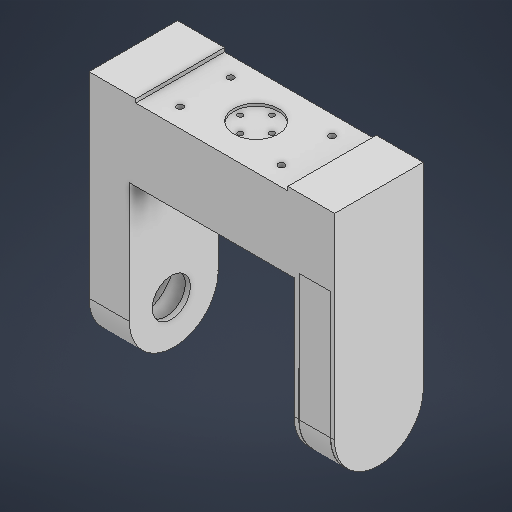
# Autodesk Inventor part: U_support
Saved by Autodesk Inventor 2026.1 (Build 301233020, 233B)
## iProperties
Created: 2026-11-17
Part Number: U_support
Material: Generic
Document SubType Name: Modeling
Designer: matar
Density: 1 g/cm^3
Appearance: Default
Author: matar
Autodesk Inventor part; units mm, degrees
ref_plane "YZ Plane" through (0, 0, 0) normal (1, 0, 0) x (0, 1, 0)
ref_plane "XZ Plane" through (0, 0, 0) normal (0, 1, 0) x (-1, 0, 0)
ref_plane "XY Plane" through (0, 0, 0) normal (0, 0, 1) x (1, 0, 0)
sketch "Sketch1" plane through (0, 0, 0) normal (0, 1, 0) x (-1, 0, 0)
  line L0 (0, 0) -> (130, 0)
  line L1 (130, 0) -> (130, -70)
  line L2 (130, -70) -> (0, -70)
  line L3 (0, -70) -> (0, 0)
  dimension "d0" = 130
  dimension "d1" = 70
  constraints: 8 end point, 2 parallel, 1 horizontal, 1 perpendicular
  measures "d0" distance of L1.end L2.end
  measures "d1" distance of L0.end L1.end
extrude "Extrusion1" add sketch "Sketch1" along normal blind 5
sketch "Sketch4" plane through (0, 0, 0) normal (1, 0, 0) x (0, 0, -1)
  line L0 (70, 5) -> (0, 5) projected
  line L1 (70, 5) -> (0, 5)
  line L2 (0, 5) -> (0, -95)
  line L3 (70, 5) -> (70, -95)
  arc A0 (0, -95) -> (70, -95) centre (35, -95) ccw
  point P0 (0, 0)
  dimension "d10" = 100
  constraints: 6 end point, 2 point on circle, 2 tangent, 1 centre point, 1 collinear, 1 perpendicular, 1 vertical
  measures "d10" distance of L0.start L3.end
sketch "Sketch5" plane through (-130, 0, -70) normal (-1, 0, 0) x (0, 0, 1)
  line L0 (0, 5) -> (70, 5) projected
  line L1 (70, -95) -> (70, 5)
  line L2 (70, 5) -> (0, 5)
  line L3 (0, 5) -> (0, -95)
  arc A0 (0, -95) -> (70, -95) centre (35, -95) ccw
  point P0 (70, 0)
  dimension "d8" = 100
  dimension "d9" = 35
  constraints: 6 end point, 2 perpendicular, 2 point on circle, 2 tangent, 1 centre point, 1 vertical
  measures "d8" distance of L1.start L0.end
  measures "d9" radius of A0
extrude "Extrusion2" add sketch "Sketch5" along normal blind 4
extrude "Extrusion3" add sketch "Sketch4" along normal blind 4
sketch "Sketch6" plane through (-134, 0, -70) normal (-1, 0, 0) x (0, 0, 1)
  line L0 (0, -95) -> (0, 5) projected
  line L1 (0, 5) -> (0, -95)
  line L2 (70, 5) -> (70, -95)
  arc A0 (0, -95) -> (70, -95) centre (35, -95) ccw projected
  arc A1 (0, -95) -> (70, -95) centre (35, -95) ccw
  arc A2 (5, -99.3497) -> (65, -99.3497) centre (35, -95) ccw
  line L3 (0, 5) -> (5, 5)
  line L4 (5, 5) -> (5, -99.3497)
  line L5 (0, 5) -> (5, 5)
  line L6 (70, 5) -> (65, 5)
  line L7 (65, 5) -> (65, -99.3497)
  line L8 (0, 5) -> (70, 5) projected
  dimension "d13" = 5
  dimension "d14" = 5
  constraints: 14 end point, 4 point on circle, 2 centre point, 2 concentric, 2 perpendicular, 1 collinear, 1 point on line
  measures "d13" distance of L0.end L3.end
  measures "d14" distance of L2.start L6.end
extrude "Extrusion4" add sketch "Sketch6" along normal blind 25 contours L0 L3 L4 A2 L7 L6 L2 A0
sketch "Sketch7" plane through (4, 0, 0) normal (1, 0, 0) x (0, 0, -1)
  line L0 (-0.1762, -95) -> (0, 5)
  line L1 (0, 5) -> (-0.1762, -95)
  line L2 (70, 5) -> (70, -98.5163)
  arc A0 (-0.1762, -95) -> (70, -98.5163) centre (35, -95) ccw
  arc A1 (-0.1762, -95) -> (70, -98.5163) centre (35, -95) ccw
  arc A2 (5, -99.3497) -> (65, -99.3497) centre (35, -95) ccw
  line L3 (0, 5) -> (5, 5)
  line L4 (5, 5) -> (5, -99.3497)
  line L5 (0, 5) -> (5, 5)
  line L6 (70, 5) -> (65, 5)
  line L7 (65, 5) -> (65, -99.3497)
  line L8 (0, 5) -> (70, 5)
  line L9 (70, -95) -> (70, 5) projected
  line L10 (70, 5) -> (0, 5) projected
  point P0 (0, 0)
  dimension "d15" = 5
  dimension "d16" = 5
  dimension "d17" = 0
  dimension "d18" = 0
  constraints: 18 end point, 6 point on circle, 3 centre point, 2 concentric, 2 perpendicular, 1 collinear, 1 point on line
  measures "d15" distance of L0.end L3.end
  measures "d16" distance of L2.start L6.end
  measures "d17" distance between parallel lines of L2 L9
  measures "d18" distance between parallel lines of L10 L8
extrude "Extrusion5" add sketch "Sketch7" along normal blind 25 contours L0 L3 L4 A2 L7 L6 L2 A0
sketch "Sketch8" plane through (-159, 0, -70) normal (-1, 0, 0) x (0, 0, 1)
  line L0 (0, 0) -> (0, -95) projected
  line L1 (0, -95) -> (0, 5)
  line L2 (70, -95) -> (70, 5) projected
  line L3 (0, 5) -> (70, 5)
  line L4 (70, 5) -> (70, -95)
  arc A0 (0, -95) -> (70, -95) centre (35, -95) ccw projected
  arc A1 (0, -95) -> (70, -95) centre (35, -95) ccw
  arc A2 (5, -99.3497) -> (65, -99.3497) centre (35, -95) ccw projected
  point P0 (70, 0)
  constraints: 6 end point, 3 point on circle, 1 centre point, 1 collinear, 1 concentric, 1 perpendicular, 1 point on line
extrude "Extrusion6" add sketch "Sketch8" along normal blind 3
sketch "Sketch9" plane through (29, 0, 0) normal (1, 0, 0) x (0, 0, -1)
  line L0 (0, -95) -> (0, 0) projected
  line L1 (0, 5) -> (70, 5) projected
  line L2 (0, -95) -> (0, 5)
  line L3 (0, 5) -> (70, 5)
  line L4 (70, 5) -> (70, -95)
  arc A0 (0, -95) -> (70, -95) centre (35, -95) ccw projected
  arc A1 (0, -95) -> (70, -95) centre (35, -95) ccw
  point P0 (0, 0)
  constraints: 6 end point, 3 point on circle, 1 centre point, 1 collinear, 1 concentric, 1 perpendicular, 1 vertical
extrude "Extrusion7" add sketch "Sketch9" along normal blind 3
sketch "Sketch10" plane through (-130, 0, -70) normal (1, 0, 0) x (0, 0, -1)
  circle A0 centre (-37, -95) radius 15
  arc A1 (-70, -95) -> (0, -95) centre (-35, -95) ccw projected
  point P0 (-70, 0)
  dimension "d25" = 30
  dimension "d26" = 0
  constraints: 1 centre point
  measures "d25" diameter of A0
  measures "d26" vertical distance of A1.centre A0.centre
extrude "Extrusion8" cut sketch "Sketch10" against normal blind 5
sketch "Sketch11" plane through (0, 0, 0) normal (-1, 0, 0) x (0, 0, 1)
  circle A0 centre (-35, -95) radius 15
  arc A1 (-70, -95) -> (0, -95) centre (-35, -95) ccw projected
  line L0 (0, 0) -> (0, -95) projected
  dimension "d29" = 30
  dimension "d30" = 0
  dimension "d31" = 35
  constraints: 1 centre point
  measures "d29" diameter of A0
  measures "d30" distance of A1.centre A0.centre
  measures "d31" distance from line of L0 A0.centre
extrude "Extrusion9" cut sketch "Sketch11" against normal blind 6
sketch "Sketch12" plane through (0, 5, 0) normal (0, 1, 0) x (1, 0, 0)
  line L0 (4, 70) -> (32, 70)
  line L1 (32, 70) -> (32, 0)
  line L2 (32, 0) -> (-162, 0)
  line L3 (-162, 0) -> (-162, 70)
  line L4 (-162, 70) -> (-116, 70)
  line L5 (-159, 5) -> (29, 5)
  line L6 (29, 5) -> (29, 65)
  line L7 (29, 65) -> (4, 65)
  line L8 (4, 65) -> (4, 70)
  line L9 (-116, 70) -> (-116, 65)
  line L10 (-116, 65) -> (-159, 65)
  line L11 (-159, 5) -> (-159, 65) projected
  line L12 (-159, 5) -> (-159, 65)
  line L13 (4, 0) -> (4, 70) projected
  point P0 (0, 0)
  dimension "d36" = 120
  dimension "d39" = 0
  constraints: 24 end point, 6 perpendicular, 2 point on line, 2 vertical
  measures "d36" distance between parallel lines of L9 L8
  measures "d39" distance between parallel lines of L8 L13
extrude "Extrusion10" add sketch "Sketch12" along normal blind 45 contours L0 L1 L2 L13 L5 L6 L7 L8 | L13 L2 L3 L4 L9 L10 L11 L5
sketch "Sketch13" plane through (0, 50, 0) normal (0, 1, 0) x (1, 0, 0)
  line L0 (-116, 70) -> (-162, 70) projected
  line L1 (32, 0) -> (-162, 0)
  line L2 (-162, 0) -> (-162, 70)
  line L3 (-162, 70) -> (32, 70)
  line L4 (32, 70) -> (32, 0)
  point P0 (0, 0)
  constraints: 8 end point, 2 parallel, 1 horizontal, 1 perpendicular
extrude "Extrusion11" add sketch "Sketch13" along normal blind 10
sketch "Sketch14" plane through (0, 60, 0) normal (0, 1, 0) x (1, 0, 0)
  circle A0 centre (-65, 35) radius 17.5
  line L0 (-162, 70) -> (-162, 0) projected
  line L1 (-162, 0) -> (32, 0) projected
  point P0 (0, 0)
  dimension "d42" = 35
  dimension "d43" = 97
  dimension "d44" = 35
  constraints: 1 centre point
  measures "d42" diameter of A0
  measures "d43" distance from line of L0 A0.centre
  measures "d44" distance from line of L1 A0.centre
extrude "Extrusion12" cut sketch "Sketch14" against normal blind 5
sketch "Sketch18" plane through (0, 60, 0) normal (0, 1, 0) x (1, 0, 0)
  line L0 (-5, 70) -> (-125, 70)
  line L1 (-125, 70) -> (-125, 0)
  line L2 (-125, 0) -> (-5, 0)
  line L3 (-5, 0) -> (-5, 70)
  line L4 (32, 0) -> (32, 70) projected
  dimension "d50" = 120
  dimension "d51" = 70
  dimension "d52" = 37
  constraints: 8 end point, 2 parallel, 1 horizontal, 1 perpendicular
  measures "d50" distance of L1.end L2.end
  measures "d51" distance of L0.end L1.end
  measures "d52" distance between parallel lines of L4 L3
extrude "Extrusion14" cut sketch "Sketch18" against normal blind 3
sketch "Sketch19" plane through (0, 57, 0) normal (0, 1, 0) x (1, 0, 0)
  circle A0 centre (-105, 55) radius 2.5
  circle A1 centre (-25, 55) radius 2.5
  circle A2 centre (-25, 15) radius 2.5
  circle A3 centre (-105, 15) radius 2.5
  line L0 (-5, 70) -> (-5, 0) projected
  line L1 (-5, 0) -> (-125, 0) projected
  line L2 (-125, 70) -> (-5, 70) projected
  line L3 (-125, 0) -> (-125, 70) projected
  point P0 (0, 0)
  dimension "d64" = 5
  dimension "d65" = 20
  dimension "d66" = 20
  dimension "d67" = 15
  dimension "d68" = 15
  dimension "d69" = 15
  dimension "d70" = 20
  dimension "d71" = 20
  dimension "d72" = 15
  constraints: 4 centre point
  measures "d64" diameter of A0
  measures "d65" distance from line of A2.centre L0
  measures "d66" distance from line of L0 A1.centre
  measures "d67" distance from line of L1 A2.centre
  measures "d68" distance from line of L2 A1.centre
  measures "d69" distance from line of L1 A3.centre
  measures "d70" distance from line of L3 A3.centre
  measures "d71" distance from line of L3 A0.centre
  measures "d72" distance from line of L2 A0.centre
extrude "Extrusion15" cut sketch "Sketch19" against normal blind 10 contours A0 | A1 | A2 | A3
sketch "Sketch20" plane through (-65, 55, -35) normal (0, 1, 0) x (1, 0, 0)
  circle A0 centre (0, -12.5) radius 2
  circle A1 centre (-12.5, 0) radius 2
  circle A2 centre (0, 12.5) radius 2
  circle A3 centre (12.5, 0) radius 2
  circle A4 centre (0, 0) radius 17.5 projected
  point P0 (65, -35)
  dimension "d75" = 4
  dimension "d76" = 12.5
  dimension "d77" = 12.5
  dimension "d78" = 12.5
  dimension "d79" = 12.5
  dimension "d80" = 4
  dimension "d81" = 4
  constraints: 4 centre point
  measures "d75" diameter of A2
  measures "d76" distance of A4.centre A3.centre
  measures "d77" distance of A4.centre A2.centre
  measures "d78" distance of A4.centre A0.centre
  measures "d79" distance of A4.centre A1.centre
  measures "d80" diameter of A0
  measures "d81" diameter of A3
extrude "Extrusion16" cut sketch "Sketch20" against normal blind 10 contours A0 | A1 | A2 | A3
body "Solid1"
